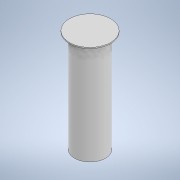
# Autodesk Inventor part: suport monede
Saved by Autodesk Inventor 2022.6 (Build 266554000, 554)
## iProperties
Created: 2026-09-04
Part Number: suport monede
Material: Generic
Document SubType Name: Modeling
Designer: Dragos Macovei
Density: 1 g/cm^3
Appearance: Default
Author: Dragos Macovei
Autodesk Inventor part; units mm, degrees
ref_plane "YZ Plane" through (0, 0, 0) normal (1, 0, 0) x (0, 1, 0)
ref_plane "XZ Plane" through (0, 0, 0) normal (0, 1, 0) x (-1, 0, 0)
ref_plane "XY Plane" through (0, 0, 0) normal (0, 0, 1) x (1, 0, 0)
sketch "Sketch1" plane through (0, 0, 0) normal (0, 1, 0) x (-1, 0, 0)
  circle A0 centre (0, 0) radius 12.5
  circle A1 centre (0, 0) radius 15
  dimension "d0" = 25
  dimension "d1" = 30
  constraints: 2 centre point, 2 coincident
  measures "d0" diameter of A0
  measures "d1" diameter of A1
extrude "Extrusion1" add sketch "Sketch1" along normal blind 100
sketch "Sketch2" plane through (0, 100, 0) normal (0, 1, 0) x (1, 0, 0)
  circle A0 centre (0, 0) radius 12.5 projected
  circle A1 centre (0, 0) radius 15 projected
  circle A2 centre (0, 0) radius 12.5 projected
extrude "Extrusion2" add sketch "Sketch2" against normal blind 2 contours A0
sketch "Sketch3" plane through (0, 0, 0) normal (0, -1, 0) x (1, 0, 0)
  line L0 (-6, -17.2653) -> (6, -17.2653)
  line L1 (6, -17.2653) -> (6, -6.4898)
  line L2 (6, -6.4898) -> (-6, -6.4898)
  line L3 (-6, -6.4898) -> (-6, -17.2653)
  circle A0 centre (0, 0) radius 15 projected
  circle A1 centre (0, 0) radius 12.5 projected
  circle A2 centre (0, 0) radius 12.5 projected
  circle A3 centre (0, 0) radius 15 projected
  point P0 (0, -12.5)
  point P1 (0, -15)
  point P2 (6, -10.9659)
  point P3 (-6, -10.9659)
  point P4 (-6, -13.7477)
  point P5 (6, -13.7477)
  dimension "d6" = 6
  dimension "d7" = 6
  constraints: 8 end point, 2 parallel, 2 vertical alignment, 1 horizontal, 1 perpendicular, 2 other
  measures "d6" distance from line of point (0, -12.5) L3
  measures "d7" distance from line of point (0, -12.5) L1
extrude "Extrusion3" cut sketch "Sketch3" against normal up to surface (98 mm away) contours L3 A1 L1 A0 picked at (-4.2544, -13.4572)
fillet "Fillet1" radius 5 4 edges at (6, 0, -12.3568) (-6, 0, -12.3568) (6, 98, -12.3568) (-6, 98, -12.3568)
sketch "Sketch4" plane through (0, 100, 0) normal (0, 1, 0) x (1, 0, 0)
  circle A0 centre (0, 0) radius 20
  dimension "d11" = 40
  constraints: 1 centre point, 1 coincident
  measures "d11" diameter of A0
extrude "Extrusion4" add sketch "Sketch4" against normal blind 1
fillet "Fillet2" radius 2 1 edges at (15, 99, 0)
equation "\"d7\" = d6"
body "Solid1"
